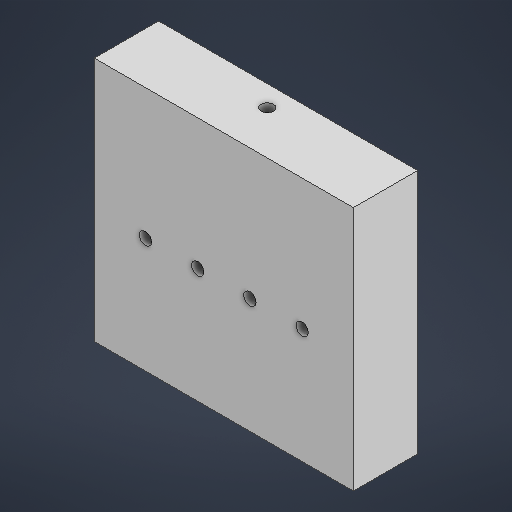
# Autodesk Inventor part: coffin_4Q_top
Saved by Autodesk Inventor 2026.2 (Build 302298010, 298A)
## iProperties
Created: 2026-11-02
Part Number: coffin_4Q_top
Material: Generic
Document SubType Name: Modeling
Designer: epm114
Mass: 47.7506 g
Surface Area: 129.218 cm^2
Volume: 47.7506 cm^3
Density: 1 g/cm^3
Appearance: Default
Author: epm114
Autodesk Inventor part; units mm, degrees
ref_plane "YZ Plane" through (0, 0, 0) normal (1, 0, 0) x (0, 1, 0)
ref_plane "XY Plane" through (0, 0, 0) normal (0, 0, 1) x (1, 0, 0)
sketch "Block_sketch" plane through (0, 0, 0) normal (0, 0, 1) x (1, 0, 0)
  line L0 (-31, -42.5) -> (31, -42.5)
  line L1 (31, -42.5) -> (31, 16.25)
  line L2 (31, 16.25) -> (-31, 16.25)
  line L3 (-31, 16.25) -> (-31, -42.5)
  point P0 (0, 0)
  dimension "d0" = 62
  dimension "d1" = 58.75
  dimension "d2" = 31
  dimension "d3" = 42.5
  constraints: 8 end point, 2 horizontal, 2 vertical
  measures "d0" distance between parallel lines of L3 L1
  measures "d1" distance between parallel lines of L0 L2
  measures "d2" horizontal distance of point (0, 0) L0.start
  measures "d3" vertical distance of point (0, 0) L0.start
extrude "Block" add sketch "Block_sketch" along normal blind 15.4
sketch "Cavity_sketch" plane through (0, 0, 0) normal (0, 0, 1) x (1, 0, 0)
  arc A0 (-25, -5.5) -> (-23, -7.5) centre (-23, -5.5) ccw
  arc A1 (23, -7.5) -> (25, -5.5) centre (23, -5.5) ccw
  arc A2 (25, 5.5) -> (23, 7.5) centre (23, 5.5) ccw
  arc A3 (-23, 7.5) -> (-25, 5.5) centre (-23, 5.5) ccw
  line L0 (-23, -7.5) -> (23, -7.5)
  line L1 (25, -5.5) -> (25, 5.5)
  line L2 (23, 7.5) -> (-23, 7.5)
  line L3 (-25, 5.5) -> (-25, -5.5)
  point P0 (0, 0)
  dimension "d6" = 50
  dimension "d7" = 15
  dimension "d8" = 2
  dimension "d9" = 2
  dimension "d10" = 2
  dimension "d11" = 2
  dimension "d12" = 23
  dimension "d13" = 5.5
  constraints: 8 end point, 8 point on circle, 8 tangent, 4 centre point, 2 horizontal, 2 vertical
  measures "d6" distance between parallel lines of L3 L1
  measures "d7" distance between parallel lines of L0 L2
  measures "d8" radius of A0
  measures "d9" radius of A1
  measures "d10" radius of A2
  measures "d11" radius of A3
  measures "d12" horizontal distance of point (0, 0) A0.centre
  measures "d13" vertical distance of point (0, 0) A0.centre
extrude "Cavity_pocket" cut sketch "Cavity_sketch" along normal blind 10.4
sketch "Chip_clearance_sketch" plane through (0, 0, 0) normal (0, 0, 1) x (1, 0, 0)
  line L0 (-22, -17.5) -> (-15.5, -17.5)
  line L1 (-15.5, -17.5) -> (-15.5, -7)
  line L2 (-15.5, -7) -> (-22, -7)
  line L3 (-22, -7) -> (-22, -17.5)
  line L4 (-9.5, -17.5) -> (-3, -17.5)
  line L5 (-3, -17.5) -> (-3, -7)
  line L6 (-3, -7) -> (-9.5, -7)
  line L7 (-9.5, -7) -> (-9.5, -17.5)
  line L8 (3, -17.5) -> (9.5, -17.5)
  line L9 (9.5, -17.5) -> (9.5, -7)
  line L10 (9.5, -7) -> (3, -7)
  line L11 (3, -7) -> (3, -17.5)
  line L12 (15.5, -17.5) -> (22, -17.5)
  line L13 (22, -17.5) -> (22, -7)
  line L14 (22, -7) -> (15.5, -7)
  line L15 (15.5, -7) -> (15.5, -17.5)
  point P0 (0, 0)
  dimension "d16" = 6.5
  dimension "d17" = 10.5
  dimension "d18" = 22
  dimension "d19" = 17.5
  dimension "d20" = 6.5
  dimension "d21" = 10.5
  dimension "d22" = 9.5
  dimension "d23" = 17.5
  dimension "d24" = 6.5
  dimension "d25" = 10.5
  dimension "d26" = 3
  dimension "d27" = 17.5
  dimension "d28" = 6.5
  dimension "d29" = 10.5
  dimension "d30" = 15.5
  dimension "d31" = 17.5
  constraints: 32 end point, 8 horizontal, 8 vertical
  measures "d16" distance between parallel lines of L3 L1
  measures "d17" distance between parallel lines of L0 L2
  measures "d18" horizontal distance of point (0, 0) L0.start
  measures "d19" vertical distance of point (0, 0) L0.start
  measures "d20" distance between parallel lines of L7 L5
  measures "d21" distance between parallel lines of L4 L6
  measures "d22" horizontal distance of point (0, 0) L4.start
  measures "d23" vertical distance of point (0, 0) L4.start
  measures "d24" distance between parallel lines of L11 L9
  measures "d25" distance between parallel lines of L8 L10
  measures "d26" horizontal distance of point (0, 0) L8.start
  measures "d27" vertical distance of point (0, 0) L8.start
  measures "d28" distance between parallel lines of L15 L13
  measures "d29" distance between parallel lines of L12 L14
  measures "d30" horizontal distance of point (0, 0) L12.start
  measures "d31" vertical distance of point (0, 0) L12.start
extrude "Chip_clearance" cut sketch "Chip_clearance_sketch" along normal blind 0.43
sketch "Drive_bores_sketch" plane through (0, 0, 0) normal (0, 0, 1) x (1, 0, 0)
  circle A0 centre (-18.75, -15) radius 1.473
  circle A1 centre (-6.25, -15) radius 1.473
  circle A2 centre (6.25, -15) radius 1.473
  circle A3 centre (18.75, -15) radius 1.473
  point P0 (0, 0)
  dimension "d34" = 2.946
  dimension "d35" = 18.75
  dimension "d36" = 15
  dimension "d37" = 2.946
  dimension "d38" = 6.25
  dimension "d39" = 15
  dimension "d40" = 2.946
  dimension "d41" = 6.25
  dimension "d42" = 15
  dimension "d43" = 2.946
  dimension "d44" = 18.75
  dimension "d45" = 15
  constraints: 4 centre point
  measures "d34" diameter of A0
  measures "d35" horizontal distance of point (0, 0) A0.centre
  measures "d36" vertical distance of point (0, 0) A0.centre
  measures "d37" diameter of A1
  measures "d38" horizontal distance of point (0, 0) A1.centre
  measures "d39" vertical distance of point (0, 0) A1.centre
  measures "d40" diameter of A2
  measures "d41" horizontal distance of point (0, 0) A2.centre
  measures "d42" vertical distance of point (0, 0) A2.centre
  measures "d43" diameter of A3
  measures "d44" horizontal distance of point (0, 0) A3.centre
  measures "d45" vertical distance of point (0, 0) A3.centre
extrude "Drive_bores" cut sketch "Drive_bores_sketch" along normal through all
ref_plane "RO_face_plane" through (0, 16.25, 0) normal (0, 1, 0) x (-1, 0, 0)
sketch "Readout_bores_sketch" plane through (0, 16.25, 0) normal (0, 1, 0) x (-1, 0, 0)
  circle A0 centre (0, 5) radius 1.473
  point P0 (0, 0)
  dimension "d49" = 2.946
  dimension "d50" = 5
  constraints: 1 centre point
  measures "d49" diameter of A0
  measures "d50" distance of point (0, 0) A0.centre
extrude "Readout_bores" cut sketch "Readout_bores_sketch" against normal blind 9.25
equation "\"d0\" = block_L"
equation "\"d1\" = y_back + y_front"
equation "\"d2\" = 0.5 * block_L"
equation "\"d3\" = y_back"
equation "\"d4\" = 0.5 * block_H"
equation "\"d6\" = cav_L"
equation "\"d7\" = cav_W"
equation "\"d8\" = cav_r"
equation "\"d9\" = cav_r"
equation "\"d10\" = cav_r"
equation "\"d11\" = cav_r"
equation "\"d12\" = -cav_r + 0.5 * cav_L"
equation "\"d13\" = -cav_r + 0.5 * cav_W"
equation "\"d14\" = 0.5 * cav_H"
equation "\"d16\" = tunnel_W"
equation "\"d17\" = top_pocket_L + ovl"
equation "\"d18\" = 0.5 * tunnel_W - q1_x"
equation "\"d19\" = 0.5 * cav_W + top_pocket_L"
equation "\"d20\" = tunnel_W"
equation "\"d21\" = top_pocket_L + ovl"
equation "\"d22\" = 0.5 * tunnel_W - q2_x"
equation "\"d23\" = 0.5 * cav_W + top_pocket_L"
equation "\"d24\" = tunnel_W"
equation "\"d25\" = top_pocket_L + ovl"
equation "\"d26\" = q3_x - 0.5 * tunnel_W"
equation "\"d27\" = 0.5 * cav_W + top_pocket_L"
equation "\"d28\" = tunnel_W"
equation "\"d29\" = top_pocket_L + ovl"
equation "\"d30\" = q4_x - 0.5 * tunnel_W"
equation "\"d31\" = 0.5 * cav_W + top_pocket_L"
equation "\"d32\" = top_pocket_D"
equation "\"d34\" = drive_dia"
equation "\"d35\" = -q1_x"
equation "\"d36\" = 0.5 * cav_W + drive_dy"
equation "\"d37\" = drive_dia"
equation "\"d38\" = -q2_x"
equation "\"d39\" = 0.5 * cav_W + drive_dy"
equation "\"d40\" = drive_dia"
equation "\"d41\" = q3_x"
equation "\"d42\" = 0.5 * cav_W + drive_dy"
equation "\"d43\" = drive_dia"
equation "\"d44\" = q4_x"
equation "\"d45\" = 0.5 * cav_W + drive_dy"
equation "\"d49\" = ro_dia"
equation "\"d50\" = ro2_z"
equation "\"d51\" = ro_port_len + ovl"
equation "\"cav_L\" = 50"
equation "\"cav_W\" = 15"
equation "\"cav_H\" = 20.8"
equation "\"cav_r\" = 2"
equation "\"wall_x\" = 6"
equation "\"wall_z\" = 5"
equation "\"wall_back\" = 5"
equation "\"chip_T\" = 0.5"
equation "\"tunnel_W\" = 6.5"
equation "\"tunnel_r\" = 0"
equation "\"q1_x\" = -0.375 * cav_L"
equation "\"q2_x\" = -0.125 * cav_L"
equation "\"q3_x\" = 0.125 * cav_L"
equation "\"q4_x\" = 0.375 * cav_L"
equation "\"top_pocket_L\" = 10"
equation "\"top_pocket_D\" = 0.43"
equation "\"drive_dia\" = 2.946"
equation "\"drive_dy\" = 7.5"
equation "\"ro_dia\" = 2.946"
equation "\"ro_port_len\" = 8.75"
equation "\"ro1_x\" = 0"
equation "\"ro1_z\" = -5"
equation "\"ro2_x\" = 0"
equation "\"ro2_z\" = 5"
equation "\"ovl\" = 0.5"
equation "\"block_L\" = cav_L + 2 * wall_x"
equation "\"block_H\" = cav_H + 2 * wall_z"
equation "\"y_front\" = 0.5 * cav_W + ro_port_len"
equation "\"y_back\" = tunnel_L + 0.5 * cav_W + wall_back"
equation "\"d48\" = y_front"
equation "\"tunnel_L\" = 30"
body "Solid1"
